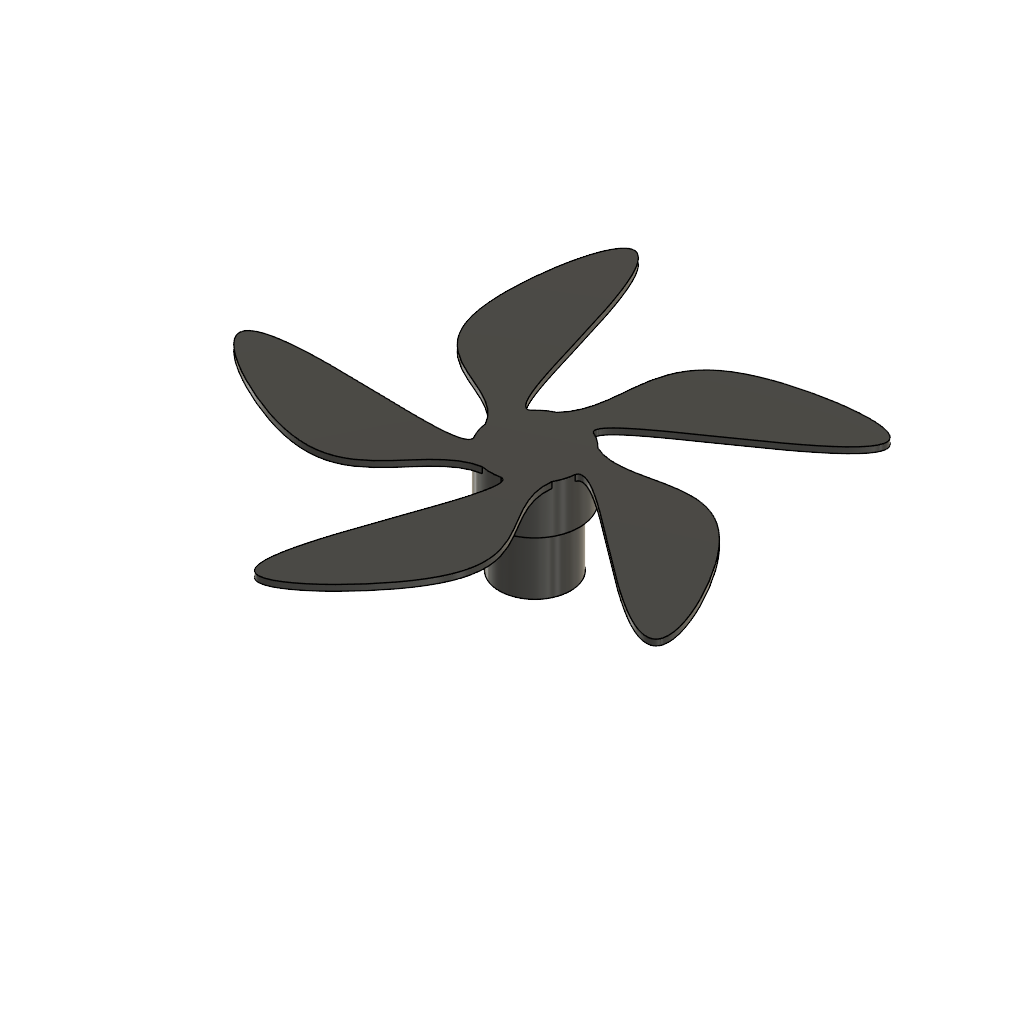
robot_desherbeur_assemblage (Autodesk Fusion 360 archive; units mm, degrees)
design "outil_desherbeur"
part number: 2026-11-26-21-03-43-981
Autodesk Fusion 360 part; units mm, degrees
sketch "Esquisse1" plane through (0, 0, 0) normal (0, 0, 1) x (1, 0, 0)
  circle A0 centre (0, 0) radius 5
  circle A1 centre (0, 0) radius 6
  dimension "d1" = 10
  dimension "d2" = 1
  constraint coincident A0.centre A1.centre
  measures "d1" diameter of A0
extrude "Extrusion1" add sketch "Esquisse1" along normal blind 10
sketch "Esquisse2" plane through (0, 0, 10) normal (0, 0, 1) x (-1, 0, 0)
  circle A0 centre (0, 0) radius 5
  circle A1 centre (0, 0) radius 6
  circle A2 centre (0, 0) radius 7.5
  dimension "d5" = 15
  constraint concentric A0 A2
  measures "d5" diameter of A2
extrude "Extrusion2" add sketch "Esquisse2" along normal blind 8 contours A0 | A1 | A2
sketch "Esquisse3" plane through (0, 0, 18) normal (0, 0, 1) x (-1, 0, 0)
  circle A0 centre (0, 0) radius 7.5
  spline S0 degree 5 poles (-5.5094, -5.0889) (-5.8529, -4.9208) (-6.5664, -4.6305) (-7.7163, -4.333) (-9.4092, -4.2132) (-11.787, -4.4898) (-14.4105, -5.0832) (-17.2424, -5.7614) (-20.2208, -6.1495) (-23.2691, -5.8424) (-26.3152, -4.5128) (-29.2821, -1.9949) (-32.1513, 1.5561) (-34.8127, 5.7221) (-37.0238, 10.0047) (-38.5066, 13.8591) (-38.9904, 16.7861) (-38.2776, 18.3991) (-36.301, 18.5038) (-33.1852, 17.1723) (-29.1946, 14.6759) (-24.6877, 11.4227) (-20.0699, 7.8951) (-15.749, 4.5903) (-12.0883, 1.9579) (-9.3626, 0.3415) (-8.037, -0.0042) (-7.5407, 0.2912) (-7.4306, 0.734) (-7.4307, 1.0168) knots 0 0 0 0 0 0 0.04 0.08 0.12 0.16 0.2 0.24 0.28 0.32 0.36 0.4 0.44 0.48 0.52 0.56 0.6 0.64 0.68 0.72 0.76 0.8 0.84 0.88 0.92 0.96 1 1 1 1 1 1
  line L0 (-27, -4) -> (-31, 0)
  point P0 (-14, -5)
  point P1 (-29, -2)
  point P2 (-38, 18)
  point P3 (-12, 2)
  constraint coincident A0 S0.start
  constraint coincident A0 S0.end
  constraint midpoint P1 L0
extrude "Extrusion3" add sketch "Esquisse3" against normal blind 1 contours A0 S0 picked at (-25.2266, 6.4637)
pattern_circular "Réseau C1" count 5 over 360 about axis through (0, 0, 18) along (0, 0, 1) of "Extrusion3"

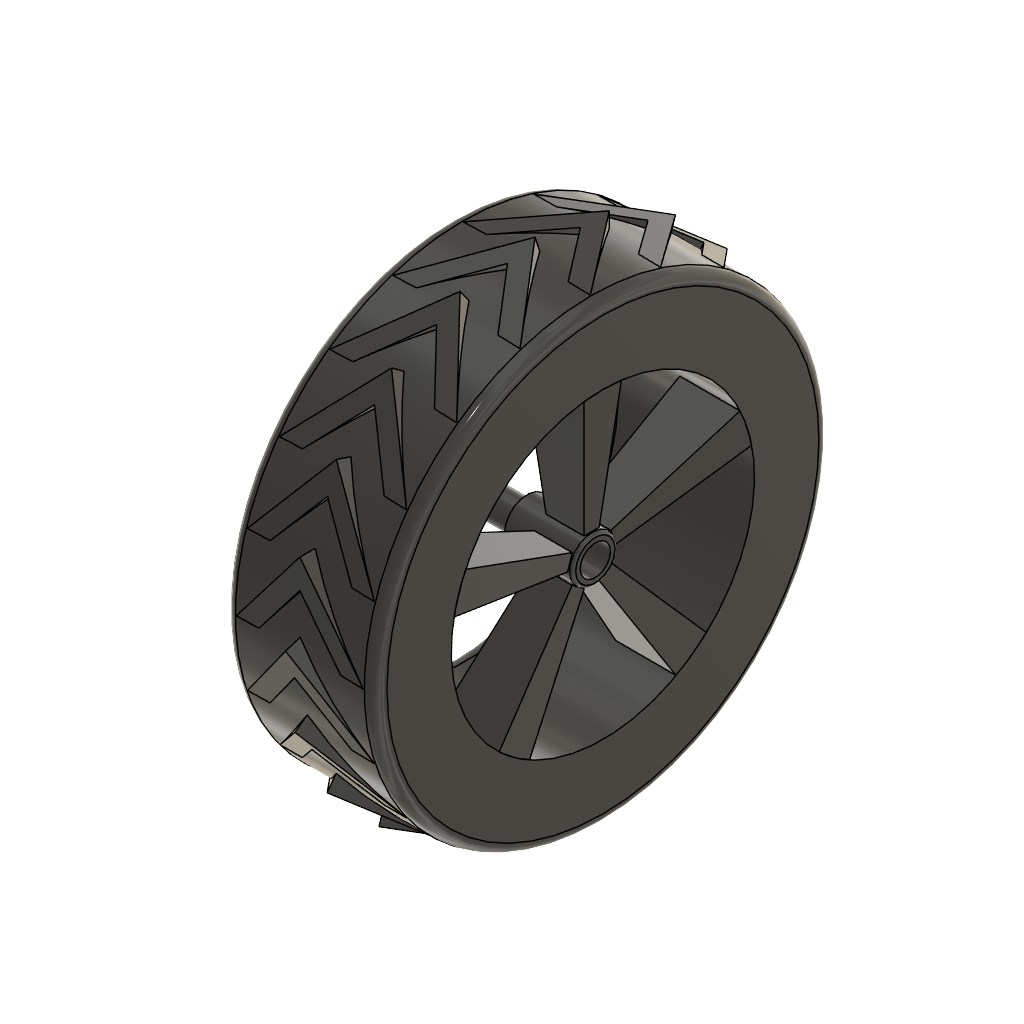
design "roue_desherbeur"
part number: 2026-11-26-21-45-35-368
Autodesk Fusion 360 part; units mm, degrees
sketch "Esquisse3" plane through (0, 0, 0) normal (0, 1, 0) x (1, 0, 0)
  line L0 (-30, -30) -> (30, -30) construction
  line L1 (0, -30) -> (-10, -30)
  line L2 (0, -30) -> (10, -30)
  line L3 (-10, -30) -> (-10, -20)
  line L4 (-10, -20) -> (10, -20)
  line L5 (10, -20) -> (10, -30)
  dimension "d8" = 30
  dimension "d11" = 10
  dimension "d12" = 10
  dimension "d13" = 10
  constraint horizontal L0
  constraint midpoint L0 L1.start
  constraint parallel L0 L1
  constraint parallel L0 L2
  constraint perpendicular L1 L3
  constraint perpendicular L3 L4
  measures "d8" distance of origin L0
  measures "d11" distance of L1.start L1.end
  measures "d12" distance of L1.start L2.end
  measures "d13" distance of L1.end L3.end
revolve "Révolution1" add sketch "Esquisse3" angle 360 about axis through (1.75, 0, 0) along (1, 0, 0) makes body 1
ref_plane "Plan de construction1" through (2.2965, 0, 30) normal (0, 0, 1) x (0, -1, 0)
sketch "Esquisse4" plane through (0, 0, 30) normal (0, 0, 1) x (1, 0, 0)
  line L0 (-8.3845, -0.0572) -> (0, 10.8426)
  line L1 (0, 7.0267) -> (-5.3856, 0.0253)
  line L2 (-5.3856, 0.0253) -> (-8.3845, -0.0572)
  line L3 (0, 1.75) -> (0, 22.5)
  line L4 (0, 7.0267) -> (5.3856, 0.0253)
  line L5 (5.3856, 0.0253) -> (8.3845, -0.0572)
  line L6 (8.3845, -0.0572) -> (0, 10.8426)
  dimension "d18" = 3
  constraint parallel L0 L1
  constraint symmetric L0.start L3 L5.end
  constraint symmetric L1.end L3 L4.end
  measures "d18" distance of L0.start L1.end
extrude "Extrusion3" add sketch "Esquisse4" along normal up to surface end surface at (-3.3333, 1.4954, 29.9627) on bodies 1 bodies 1
pattern_circular "Réseau C1" count 20 over 360 about axis through (10, 0, 0) along (-1, 0, 0) of "Extrusion3"
fillet "Congé1" radius 1.5 2 edges at (10, -10.8485, -27.9698) (-10, -10.8485, -27.9698) on bodies 1
sketch "Esquisse5" plane through (0, 0, 0) normal (1, 0, 0) x (0, 1, 0)
  circle A0 centre (0, 0) radius 1.5
  circle A1 centre (0, 0) radius 2
  dimension "d26" = 3
  dimension "d27" = 4
  constraint coincident A0.centre A1.centre
  constraint concentric A0 A1
  measures "d26" diameter of A0
  measures "d27" diameter of A1
extrude "Extrusion4" add sketch "Esquisse5" against normal blind 10 separate body contours A0 | A1 makes body 2
extrude "Extrusion5" add sketch "Esquisse5" against normal blind 14 bodies 2
sketch "Esquisse6" plane through (0, 0, 0) normal (1, 0, 0) x (0, 1, 0)
  circle A0 centre (0, 0) radius 2
  circle A1 centre (0, 0) radius 3
  dimension "d32" = 6
  constraint coincident A0.centre A1.centre
  measures "d32" diameter of A1
extrude "Extrusion6" add sketch "Esquisse6" along normal blind 9 contours A0 | A1 bodies 2
sketch "Esquisse7" plane through (9, 0, 0) normal (1, 0, 0) x (0, 1, 0)
  circle A0 centre (0, 0) radius 3
  circle A1 centre (0, 0) radius 2
  constraint coincident A0.centre A1.centre
extrude "Extrusion7" cut sketch "Esquisse7" against normal blind 5 contours A1 bodies 2
ref_plane "Plan de construction2" through (3.7401, 0, 3) normal (0, 0, 1) x (0, 1, 0)
sketch "Esquisse8" plane through (0, 0, 3) normal (0, 0, 1) x (1, 0, 0)
  line L0 (8.5, -1) -> (3.5, -1)
  line L1 (3.5, -1) -> (3.5, 1)
  line L2 (3.5, 1) -> (8.5, 1)
  line L3 (8.5, 1) -> (8.5, -1)
  line L4 (8.5, -1) -> (3.5, 1) construction
  line L5 (3.5, -1) -> (8.5, 1) construction
  point P0 (6, 0)
  dimension "d39" = 5
  dimension "d40" = 2
  constraint horizontal L0
  constraint perpendicular L0 L1
  constraint parallel L0 L2
  constraint parallel L1 L3
  constraint coincident L4 P0
  constraint coincident L5 P0
  measures "d39" distance of L1.end L2.end
  measures "d40" distance of L0.end L1.end
extrude "Extrusion8" add sketch "Esquisse8" along normal up to surface draft 5 end surface at (-3.3333, 0.9969, 19.9751) on bodies 1 bodies 1 2
pattern_circular "Réseau C2" count 5 over 360 about axis through (9, 0, 0) along (1, 0, 0) of "Extrusion8"
fillet "Congé2" radius 0.4 1 edges at (9, -2.797, -1.0848) on bodies 1
fillet "Congé3" radius 2 1 edges at (-10, -7.2323, -18.6465) on bodies 1

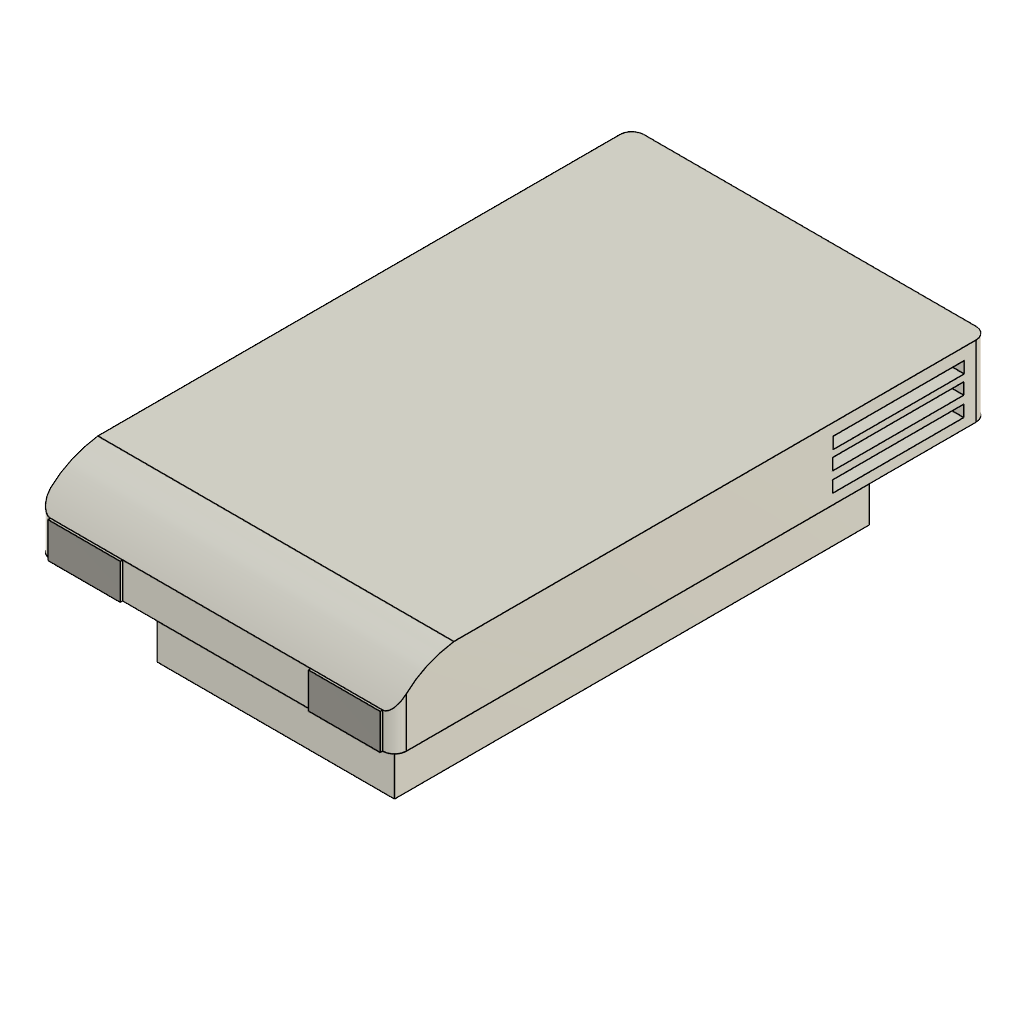
design "robot_desherbeur"
part number: 2026-11-26-20-07-29-653
Autodesk Fusion 360 part; units mm, degrees
sketch "Esquisse1" plane through (0, 0, 0) normal (0, 0, 1) x (1, 0, 0)
  line L0 (50, -100) -> (-50, -100)
  line L1 (-50, -100) -> (-50, 100)
  line L2 (-50, 100) -> (50, 100)
  line L3 (50, 100) -> (50, -100)
  line L4 (50, -100) -> (-50, 100) construction
  line L5 (-50, -100) -> (50, 100) construction
  dimension "d1" = 100
  dimension "d2" = 200
  constraint horizontal L0
  constraint perpendicular L0 L1
  constraint parallel L0 L2
  constraint parallel L1 L3
  constraint coincident L4 origin
  constraint coincident L5 origin
  measures "d1" distance of L1.end L2.end
  measures "d2" distance of L0.end L1.end
extrude "Extrusion1" add sketch "Esquisse1" along normal blind 40
shell "Coque1" thickness 2 removed faces 1 at (16.6667, -33.3333, 40)
ref_plane "Plan de construction1" through (0, 0, 40) normal (0, 0, 1) x (1, 0, 0)
sketch "Esquisse2" plane through (0, 0, 40) normal (0, 0, 1) x (1, 0, 0)
  line L0 (75, -125) -> (-75, -125)
  line L1 (-75, -125) -> (-75, 125)
  line L2 (-75, 125) -> (75, 125)
  line L3 (75, 125) -> (75, -125)
  line L4 (75, -125) -> (-75, 125) construction
  line L5 (-75, -125) -> (75, 125) construction
  dimension "d8" = 150
  dimension "d9" = 250
  constraint horizontal L0
  constraint perpendicular L0 L1
  constraint parallel L0 L2
  constraint parallel L1 L3
  constraint coincident L4 origin
  constraint coincident L5 origin
extrude "Extrusion2" add sketch "Esquisse2" along normal blind 30
sketch "Esquisse3" plane through (75, 0, 0) normal (1, 0, 0) x (0, 1, 0)
  line L0 (-125, 40) -> (125, 40)
  line L1 (125, 40) -> (125, 70)
  line L2 (125, 70) -> (-125, 70)
  line L3 (-125, 70) -> (-125, 40)
  line L4 (59.7923, 65) -> (115, 65)
  line L5 (115, 65) -> (115, 60.1222)
  line L6 (115, 60.1222) -> (59.7923, 60.1222)
  line L7 (59.7923, 60.1222) -> (59.7923, 65)
  line L8 (114.8036, 52.4629) -> (59.5959, 52.4629)
  line L9 (59.5959, 52.4629) -> (59.5959, 57.3407)
  line L10 (59.5959, 57.3407) -> (114.8036, 57.3407)
  line L11 (114.8036, 57.3407) -> (114.8036, 52.4629)
  line L12 (114.8036, 44.3126) -> (59.5959, 44.3126)
  line L13 (59.5959, 44.3126) -> (59.5959, 49.1904)
  line L14 (59.5959, 49.1904) -> (114.8036, 49.1904)
  line L15 (114.8036, 49.1904) -> (114.8036, 44.3126)
  constraint horizontal L4
  constraint vertical L5
  constraint horizontal L6
  constraint vertical L7
  constraint horizontal L10
  constraint vertical L11
  constraint horizontal L8
  constraint vertical L9
  constraint horizontal L14
  constraint vertical L15
  constraint horizontal L12
  constraint vertical L13
extrude "Extrusion6" cut sketch "Esquisse3" against normal blind 250 contours L4 L5 L6 L7 | L8 L9 L10 L11 | L12 L13 L14 L15
sketch "Esquisse4" plane through (0, 0, 0) normal (1, 0, 0) x (0, 1, 0)
  line L0 (125, 70) -> (-125, 70)
  line L1 (-125, 70) -> (-125, 40)
  line L2 (-125, 40) -> (125, 40)
  spline S0 degree 5 poles (-74.0098, 70) (-76.3613, 70.261) (-81.0281, 70.6829) (-87.9196, 71.0155) (-96.8756, 70.8171) (-107.4933, 68.9754) (-115.2346, 65.424) (-120.4044, 61.0043) (-123.5228, 57.1525) (-125, 55) knots 0 0 0 0 0 0 0.2 0.4 0.6 0.8 1 1 1 1 1 1
  line L3 (-121.5687, 60) -> (-128.4313, 50)
  line L4 (-74.0098, 70) -> (-125, 70)
  line L5 (-125, 55) -> (-125, 70)
  constraint midpoint S0.end L3
  constraint coincident L0.end L1.start
  constraint perpendicular L1 L4
  constraint perpendicular L4 L5
  constraint midpoint L1 S0.end
extrude "Extrusion7" cut sketch "Esquisse4" along normal mid plane 400 contours L0 L1 S0 L4 L5
fillet "Congé1" radius 5 1 edges at (75, -125, 47.5)
fillet "Congé1" radius 5 1 edges at (-75, -125, 47.5)
fillet "Congé1" radius 5 2 edges at (75, 125, 55) (-75, 125, 55)
sketch "Esquisse5" plane through (0, 0, 0) normal (0, 0, -1) x (1, 0, 0)
  line L0 (-50, -100) -> (50, -100)
  line L1 (50, -100) -> (50, 100)
  line L2 (50, 100) -> (-50, 100)
  line L3 (-50, 100) -> (-50, -100)
  line L4 (0, 100) -> (0, 60) construction
  circle A0 centre (0, 60) radius 5
  dimension "d32" = 40
  dimension "d33" = 10
  constraint midpoint L2 L4.start
  constraint perpendicular L2 L4
  constraint coincident L4.end A0.centre
  measures "d32" distance of L4.start L4.end
  measures "d33" diameter of A0
extrude "Extrusion8" add sketch "Esquisse5" along normal blind 10 contours A0
sketch "Esquisse7" plane through (0, -125, 0) normal (0, -1, 0) x (1, 0, 0)
  line L0 (-70, 55) -> (-70, 40)
  line L1 (-70, 40) -> (70, 40)
  line L2 (70, 40) -> (70, 55)
  line L3 (70, 55) -> (-70, 55)
  line L4 (-39.5034, 55) -> (-39.5034, 40)
  line L5 (39.7668, 55) -> (39.7668, 40)
  constraint coincident L3 L4.start
  constraint coincident L1 L4.end
  constraint perpendicular L1 L4
  constraint coincident L3 L5.start
  constraint coincident L1 L5.end
  constraint perpendicular L1 L5
extrude "Extrusion9" add sketch "Esquisse7" along normal blind 1 contours L0 L1 L3 L4 | L1 L2 L3 L5
